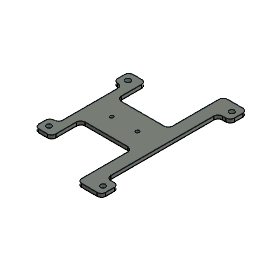
Attachment Micromouse (Autodesk Fusion 360 design; units mm, degrees)
part number: 2026-11-26-12-53-00-041
Autodesk Fusion 360 part; units mm, degrees
sketch "Sketch1" plane through (0, 0, 0) normal (0, 1, 0) x (1, 0, 0)
  line L0 (0, 0) -> (10, 0)
  line L1 (10, 0) -> (10, -17)
  line L2 (10, -17) -> (40, -17)
  line L3 (0, 0) -> (0, -9)
  line L4 (0, -9) -> (5, -9)
  line L5 (5, -9) -> (5, -46)
  line L6 (5, -46) -> (0, -46)
  line L7 (0, -46) -> (0, -55)
  line L8 (0, -55) -> (10, -55)
  line L9 (10, -55) -> (10, -38)
  line L10 (10, -38) -> (40, -38)
  line L11 (40, -38) -> (40, -70)
  line L12 (40, -17) -> (40, 15)
  line L13 (40, -70) -> (54, -70)
  line L14 (54, -70) -> (54, -60)
  line L15 (54, -60) -> (47, -60)
  line L16 (47, -60) -> (47, 5)
  line L17 (47, 5) -> (54, 5)
  line L18 (54, 5) -> (54, 15)
  line L19 (54, 15) -> (40, 15)
  dimension "d1" = 10
  dimension "d2" = 17
  dimension "d3" = 30
  dimension "d4" = 9
  dimension "d5" = 5
  dimension "d6" = 37
  dimension "d7" = 5
  dimension "d8" = 9
  dimension "d9" = 10
  dimension "d10" = 17
  dimension "d11" = 30
  dimension "d12" = 32
  dimension "d16" = 32
  dimension "d20" = 14
  dimension "d21" = 10
  dimension "d22" = 65
  dimension "d23" = 7
  dimension "d24" = 10
  constraint coincident L0.start L3.start
  constraint horizontal L0
  constraint perpendicular L0 L1
  constraint perpendicular L1 L2
  constraint perpendicular L0 L3
  constraint perpendicular L3 L4
  constraint perpendicular L4 L5
  constraint perpendicular L5 L6
  constraint perpendicular L4 L7
  constraint perpendicular L5 L8
  constraint perpendicular L4 L9
  constraint perpendicular L5 L10
  constraint perpendicular L10 L11
  constraint perpendicular L2 L12
  constraint perpendicular L11 L13
  constraint perpendicular L13 L14
  constraint perpendicular L11 L15
  constraint perpendicular L13 L16
  constraint perpendicular L16 L17
  constraint perpendicular L13 L18
  measures "d1" distance of L0.start L0.end
  measures "d2" distance of L0.end L1.end
  measures "d3" distance of L1.end L2.end
  measures "d4" distance of L0.start L3.end
  measures "d5" distance of L3.end L4.end
  measures "d6" distance of L4.end L5.end
  measures "d7" distance of L5.end L6.end
  measures "d9" distance of L7.end L8.end
  measures "d10" distance of L8.end L9.end
  measures "d11" distance of L9.end L10.end
  measures "d12" distance of L10.end L11.end
  measures "d16" distance of L2.end L12.end
  measures "d20" distance of L11.end L13.end
  measures "d21" distance of L13.end L14.end
  measures "d22" distance of L15.end L16.end
  measures "d23" distance of L16.end L17.end
  measures "d24" distance of L17.end L18.end
extrude "Extrude1" add sketch "Sketch1" along normal blind 2 makes body 1
sketch "Sketch2" plane through (0, 0, 0) normal (-1, 0, 0) x (0, 0, 1)
  line L0 (0, 0) -> (9, 0)
  line L1 (9, 0) -> (9, 2)
  line L2 (9, 2) -> (0, 2)
  line L3 (0, 2) -> (0, 0)
fillet "Fillet1" radius 2.5 1 edges at (0, 1, 0) on bodies 1
fillet "Fillet2" radius 2.5 2 edges at (0, 1, 46) (0, 1, 55) on bodies 1
fillet "Fillet3" radius 2.5 1 edges at (0, 1, 9) on bodies 1
fillet "Fillet4" radius 2.5 6 edges at (40, 1, 70) (54, 1, 70) (54, 1, 60) (54, 1, -5) (54, 1, -15) (40, 1, -15) on bodies 1
sketch "Sketch3" plane through (0, 2, 0) normal (0, 1, 0) x (-1, 0, 0)
  arc A0 (-42.5, -15) -> (-40, -12.5) centre (-42.5, -12.5) ccw
  line L0 (-40, -12.5) -> (-40, 17)
  line L1 (-40, 17) -> (-10, 17)
  line L2 (-10, 17) -> (-10, 0)
  line L3 (-10, 0) -> (-2.5, 0)
  arc A1 (-2.5, 0) -> (0, 2.5) centre (-2.5, 2.5) ccw
  line L4 (0, 2.5) -> (0, 6.5)
  arc A2 (0, 6.5) -> (-2.5, 9) centre (-2.5, 6.5) ccw
  line L5 (-2.5, 9) -> (-5, 9)
  line L6 (-5, 9) -> (-5, 46)
  line L7 (-5, 46) -> (-2.5, 46)
  arc A3 (-2.5, 46) -> (0, 48.5) centre (-2.5, 48.5) ccw
  line L8 (0, 48.5) -> (0, 52.5)
  arc A4 (0, 52.5) -> (-2.5, 55) centre (-2.5, 52.5) ccw
  line L9 (-2.5, 55) -> (-10, 55)
  line L10 (-10, 55) -> (-10, 38)
  line L11 (-10, 38) -> (-40, 38)
  line L12 (-40, 38) -> (-40, 67.5)
  arc A5 (-40, 67.5) -> (-42.5, 70) centre (-42.5, 67.5) ccw
  line L13 (-42.5, 70) -> (-51.5, 70)
  arc A6 (-51.5, 70) -> (-54, 67.5) centre (-51.5, 67.5) ccw
  line L14 (-54, 67.5) -> (-54, 62.5)
  arc A7 (-54, 62.5) -> (-51.5, 60) centre (-51.5, 62.5) ccw
  line L15 (-51.5, 60) -> (-47, 60)
  line L16 (-47, 60) -> (-47, -5)
  line L17 (-47, -5) -> (-51.5, -5)
  arc A8 (-51.5, -5) -> (-54, -7.5) centre (-51.5, -7.5) ccw
  line L18 (-54, -7.5) -> (-54, -12.5)
  arc A9 (-54, -12.5) -> (-51.5, -15) centre (-51.5, -12.5) ccw
  line L19 (-51.5, -15) -> (-42.5, -15)
  circle A10 centre (-50, -10) radius 1.5
  circle A11 centre (-50, 65) radius 1.5
  circle A12 centre (-4, 4.5) radius 1.5
  circle A13 centre (-4, 50.5) radius 1.5
  dimension "d36" = 3
  dimension "d38" = 3
  dimension "d40" = 3
  dimension "d42" = 3
  measures "d36" diameter of A10
  measures "d38" diameter of A11
  measures "d40" diameter of A12
  measures "d42" diameter of A13
extrude "Extrude2" cut sketch "Sketch3" against normal blind 3 contours A10 | A11 | A12 | A13 bodies 1
sketch "Sketch4" plane through (0, 2, 0) normal (0, 1, 0) x (-1, 0, 0)
  circle A0 centre (-50, -10) radius 1.5
  circle A1 centre (-4, 50.5) radius 1.5
  circle A2 centre (-4, 4.5) radius 1.5
  circle A3 centre (-50, 65) radius 1.5
  arc A4 (-42.5, -15) -> (-40, -12.5) centre (-42.5, -12.5) ccw
  line L0 (-40, -12.5) -> (-40, 17)
  line L1 (-40, 17) -> (-10, 17)
  line L2 (-10, 17) -> (-10, 0)
  line L3 (-10, 0) -> (-2.5, 0)
  arc A5 (-2.5, 0) -> (0, 2.5) centre (-2.5, 2.5) ccw
  line L4 (0, 2.5) -> (0, 6.5)
  arc A6 (0, 6.5) -> (-2.5, 9) centre (-2.5, 6.5) ccw
  line L5 (-2.5, 9) -> (-5, 9)
  line L6 (-5, 9) -> (-5, 46)
  line L7 (-5, 46) -> (-2.5, 46)
  arc A7 (-2.5, 46) -> (0, 48.5) centre (-2.5, 48.5) ccw
  line L8 (0, 48.5) -> (0, 52.5)
  arc A8 (0, 52.5) -> (-2.5, 55) centre (-2.5, 52.5) ccw
  line L9 (-2.5, 55) -> (-10, 55)
  line L10 (-10, 55) -> (-10, 38)
  line L11 (-10, 38) -> (-40, 38)
  line L12 (-40, 38) -> (-40, 67.5)
  arc A9 (-40, 67.5) -> (-42.5, 70) centre (-42.5, 67.5) ccw
  line L13 (-42.5, 70) -> (-51.5, 70)
  arc A10 (-51.5, 70) -> (-54, 67.5) centre (-51.5, 67.5) ccw
  line L14 (-54, 67.5) -> (-54, 62.5)
  arc A11 (-54, 62.5) -> (-51.5, 60) centre (-51.5, 62.5) ccw
  line L15 (-51.5, 60) -> (-47, 60)
  line L16 (-47, 60) -> (-47, -5)
  line L17 (-47, -5) -> (-51.5, -5)
  arc A12 (-51.5, -5) -> (-54, -7.5) centre (-51.5, -7.5) ccw
  line L18 (-54, -7.5) -> (-54, -12.5)
  arc A13 (-54, -12.5) -> (-51.5, -15) centre (-51.5, -12.5) ccw
  line L19 (-51.5, -15) -> (-42.5, -15)
  circle A14 centre (-75, 25) radius 10
  circle A15 centre (-85, 25) radius 4.5
  circle A16 centre (-65, 25) radius 4.5
  dimension "d46" = 20
  dimension "d47" = 9
  dimension "d48" = 9
  constraint coincident A14 A15.centre
  constraint coincident A14 A16.centre
  measures "d46" diameter of A14
  measures "d47" diameter of A15
  measures "d48" diameter of A16
extrude "Extrude3" add sketch "Sketch4" along normal blind 1 separate body contours A14 A16 | A14 A16 | A14 A15 A16 | A14 A15 | A14 A15 makes body 2
sketch "Sketch5" plane through (0, 3, 0) normal (0, 1, 0) x (-1, 0, 0)
  arc A0 (-66.0125, 20.6154) -> (-66.0125, 29.3846) centre (-65, 25) ccw
  arc A1 (-66.0125, 29.3846) -> (-83.9875, 29.3846) centre (-75, 25) ccw
  arc A2 (-83.9875, 29.3846) -> (-83.9875, 20.6154) centre (-85, 25) ccw
  arc A3 (-83.9875, 20.6154) -> (-66.0125, 20.6154) centre (-75, 25) ccw
  line L0 (-84, 25) -> (-75, 25)
  circle A4 centre (-66, 25) radius 1
  circle A5 centre (-84, 25) radius 1
  dimension "d51" = 9
  dimension "d52" = 9
  dimension "d59" = 2
  dimension "d60" = 2
  constraint coincident A1.centre A3.centre
  constraint coincident L0.start A5.centre
  measures "d51" distance of A1.centre L0.start
  measures "d52" distance of A1.centre A4.centre
  measures "d59" diameter of A4
  measures "d60" diameter of A5
fillet "Fillet5" radius 2.5 4 edges at (10, 1, 17) (10, 1, 38) (40, 1, 38) (40, 1, 17) on bodies 1
fillet "Fillet6" radius 2.5 2 edges at (10, 1, 55) (10, 1, 0) on bodies 1
fillet "Fillet7" radius 2.5 4 edges at (47, 1, -5) (5, 1, 9) (47, 1, 60) (5, 1, 46) on bodies 1
extrude "Extrude4" cut sketch "Sketch5" against normal blind 3 contours A4 | A5 bodies 2
sketch "Sketch6" plane through (0, 2, 0) normal (0, 1, 0) x (-1, 0, 0)
  circle A0 centre (-50, -10) radius 1.5
  circle A1 centre (-4, 50.5) radius 1.5
  circle A2 centre (-4, 4.5) radius 1.5
  circle A3 centre (-50, 65) radius 1.5
  arc A4 (-10, 2.5) -> (-7.5, 0) centre (-7.5, 2.5) ccw
  line L0 (-7.5, 0) -> (-2.5, 0)
  arc A5 (-2.5, 0) -> (0, 2.5) centre (-2.5, 2.5) ccw
  line L1 (0, 2.5) -> (0, 6.5)
  arc A6 (0, 6.5) -> (-2.5, 9) centre (-2.5, 6.5) ccw
  arc A7 (-5, 11.5) -> (-2.5, 9) centre (-2.5, 11.5) ccw
  line L2 (-5, 11.5) -> (-5, 43.5)
  arc A8 (-2.5, 46) -> (-5, 43.5) centre (-2.5, 43.5) ccw
  arc A9 (-2.5, 46) -> (0, 48.5) centre (-2.5, 48.5) ccw
  line L3 (0, 48.5) -> (0, 52.5)
  arc A10 (0, 52.5) -> (-2.5, 55) centre (-2.5, 52.5) ccw
  line L4 (-2.5, 55) -> (-7.5, 55)
  arc A11 (-7.5, 55) -> (-10, 52.5) centre (-7.5, 52.5) ccw
  line L5 (-10, 52.5) -> (-10, 40.5)
  arc A12 (-12.5, 38) -> (-10, 40.5) centre (-12.5, 40.5) ccw
  line L6 (-12.5, 38) -> (-37.5, 38)
  arc A13 (-40, 40.5) -> (-37.5, 38) centre (-37.5, 40.5) ccw
  line L7 (-40, 40.5) -> (-40, 67.5)
  arc A14 (-40, 67.5) -> (-42.5, 70) centre (-42.5, 67.5) ccw
  line L8 (-42.5, 70) -> (-51.5, 70)
  arc A15 (-51.5, 70) -> (-54, 67.5) centre (-51.5, 67.5) ccw
  line L9 (-54, 67.5) -> (-54, 62.5)
  arc A16 (-54, 62.5) -> (-51.5, 60) centre (-51.5, 62.5) ccw
  line L10 (-51.5, 60) -> (-49.5, 60)
  arc A17 (-47, 57.5) -> (-49.5, 60) centre (-49.5, 57.5) ccw
  line L11 (-47, 57.5) -> (-47, -2.5)
  arc A18 (-49.5, -5) -> (-47, -2.5) centre (-49.5, -2.5) ccw
  line L12 (-49.5, -5) -> (-51.5, -5)
  arc A19 (-51.5, -5) -> (-54, -7.5) centre (-51.5, -7.5) ccw
  line L13 (-54, -7.5) -> (-54, -12.5)
  arc A20 (-54, -12.5) -> (-51.5, -15) centre (-51.5, -12.5) ccw
  line L14 (-51.5, -15) -> (-42.5, -15)
  arc A21 (-42.5, -15) -> (-40, -12.5) centre (-42.5, -12.5) ccw
  line L15 (-40, -12.5) -> (-40, 14.5)
  arc A22 (-37.5, 17) -> (-40, 14.5) centre (-37.5, 14.5) ccw
  line L16 (-37.5, 17) -> (-12.5, 17)
  arc A23 (-10, 14.5) -> (-12.5, 17) centre (-12.5, 14.5) ccw
  line L17 (-10, 14.5) -> (-10, 2.5)
  circle A24 centre (-17.5, 27.5) radius 1
  circle A25 centre (-32.5, 27.5) radius 1
  dimension "d66" = 2
  dimension "d67" = 2
  measures "d66" diameter of A24
  measures "d67" diameter of A25
extrude "Extrude5" cut sketch "Sketch6" against normal blind 2 contours A24 | A25 bodies 1
sketch "Sketch7" plane through (0, 2, 0) normal (0, 1, 0) x (-1, 0, 0)
  circle A0 centre (-17.5, 27.5) radius 1
  circle A1 centre (-32.5, 27.5) radius 1
  circle A2 centre (-50, -10) radius 1.5
  circle A3 centre (-4, 50.5) radius 1.5
  circle A4 centre (-4, 4.5) radius 1.5
  circle A5 centre (-50, 65) radius 1.5
  arc A6 (-10, 2.5) -> (-7.5, 0) centre (-7.5, 2.5) ccw
  line L0 (-7.5, 0) -> (-2.5, 0)
  arc A7 (-2.5, 0) -> (0, 2.5) centre (-2.5, 2.5) ccw
  line L1 (0, 2.5) -> (0, 6.5)
  arc A8 (0, 6.5) -> (-2.5, 9) centre (-2.5, 6.5) ccw
  arc A9 (-5, 11.5) -> (-2.5, 9) centre (-2.5, 11.5) ccw
  line L2 (-5, 11.5) -> (-5, 43.5)
  arc A10 (-2.5, 46) -> (-5, 43.5) centre (-2.5, 43.5) ccw
  arc A11 (-2.5, 46) -> (0, 48.5) centre (-2.5, 48.5) ccw
  line L3 (0, 48.5) -> (0, 52.5)
  arc A12 (0, 52.5) -> (-2.5, 55) centre (-2.5, 52.5) ccw
  line L4 (-2.5, 55) -> (-7.5, 55)
  arc A13 (-7.5, 55) -> (-10, 52.5) centre (-7.5, 52.5) ccw
  line L5 (-10, 52.5) -> (-10, 40.5)
  arc A14 (-12.5, 38) -> (-10, 40.5) centre (-12.5, 40.5) ccw
  line L6 (-12.5, 38) -> (-37.5, 38)
  arc A15 (-40, 40.5) -> (-37.5, 38) centre (-37.5, 40.5) ccw
  line L7 (-40, 40.5) -> (-40, 67.5)
  arc A16 (-40, 67.5) -> (-42.5, 70) centre (-42.5, 67.5) ccw
  line L8 (-42.5, 70) -> (-51.5, 70)
  arc A17 (-51.5, 70) -> (-54, 67.5) centre (-51.5, 67.5) ccw
  line L9 (-54, 67.5) -> (-54, 62.5)
  arc A18 (-54, 62.5) -> (-51.5, 60) centre (-51.5, 62.5) ccw
  line L10 (-51.5, 60) -> (-49.5, 60)
  arc A19 (-47, 57.5) -> (-49.5, 60) centre (-49.5, 57.5) ccw
  line L11 (-47, 57.5) -> (-47, -2.5)
  arc A20 (-49.5, -5) -> (-47, -2.5) centre (-49.5, -2.5) ccw
  line L12 (-49.5, -5) -> (-51.5, -5)
  arc A21 (-51.5, -5) -> (-54, -7.5) centre (-51.5, -7.5) ccw
  line L13 (-54, -7.5) -> (-54, -12.5)
  arc A22 (-54, -12.5) -> (-51.5, -15) centre (-51.5, -12.5) ccw
  line L14 (-51.5, -15) -> (-42.5, -15)
  arc A23 (-42.5, -15) -> (-40, -12.5) centre (-42.5, -12.5) ccw
  line L15 (-40, -12.5) -> (-40, 14.5)
  arc A24 (-37.5, 17) -> (-40, 14.5) centre (-37.5, 14.5) ccw
  line L16 (-37.5, 17) -> (-12.5, 17)
  arc A25 (-10, 14.5) -> (-12.5, 17) centre (-12.5, 14.5) ccw
  line L17 (-10, 14.5) -> (-10, 2.5)
hidden bodies 2
